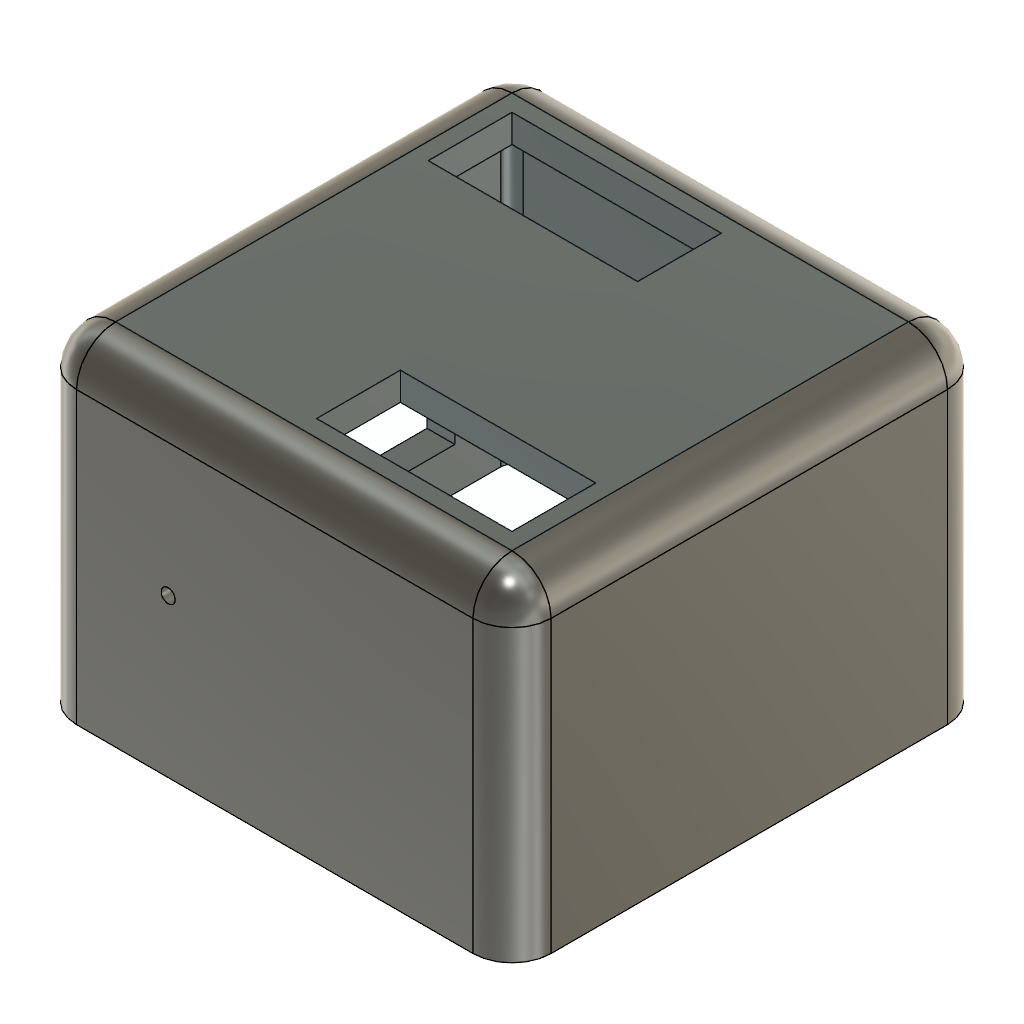
base (Autodesk Fusion 360 design; units mm, degrees)
part number: 2026-10-28-17-51-00-344
Autodesk Fusion 360 part; units mm, degrees
sketch "Sketch1" plane through (0, 0, 0) normal (0, 0, 1) x (1, 0, 0)
  line L0 (-100, 100) -> (50, 100)
  line L1 (50, 100) -> (50, -50)
  line L2 (50, -50) -> (-100, -50)
  line L3 (-100, -50) -> (-100, 100)
  dimension "d1" = 150
  dimension "d2" = 150
  constraint horizontal L0
  constraint vertical L1
  constraint horizontal L2
  constraint vertical L3
  measures "d1" distance of L0.start L0.end
  measures "d2" distance of L0.start L2.end
extrude "Extrude1" add sketch "Sketch1" along normal blind 8
fillet "Fillet1" radius 4 1 edges at (-25, 100, 8)
fillet "Fillet2" radius 4 3 edges at (50, 23, 8) (50, 98.8284, 6.8284) (50, 100, 2)
fillet "Fillet3" radius 4 3 edges at (-27, -50, 8) (48.8284, -50, 6.8284) (50, -50, 2)
fillet "Fillet4" radius 4 5 edges at (-100, 100, 2) (-100, 98.8284, 6.8284) (-100, 25, 8) (-100, -48.8284, 6.8284) (-100, -50, 2)
sketch "Sketch2" plane through (0, 0, 0) normal (0, 1, 0) x (1, 0, 0)
extrude "Extrude2" add 1 faces at (-50, 48.6667, 0) along direction (0, 0, -1) blind 100
shell "Shell1" thickness 10 outward yes removed faces 1 at (-50, 48.6667, -100)
sketch "Sketch3" plane through (0, 0, 18) normal (0, 0, 1) x (-1, 0, 0)
  line L0 (96, -96) -> (96, 46)
  line L1 (96, 46) -> (-46, 46)
  line L2 (-46, 46) -> (-46, -96)
  line L3 (-46, -96) -> (96, -96)
  line L4 (-40, 40) -> (30, 40)
  line L5 (30, 40) -> (30, 10)
  line L6 (30, 10) -> (-40, 10)
  line L7 (-40, 10) -> (-40, 40)
  line L8 (90, -90) -> (15, -90)
  line L9 (15, -90) -> (15, -60)
  line L10 (15, -60) -> (90, -60)
  line L11 (90, -60) -> (90, -90)
  dimension "d16" = 75
  dimension "d17" = 30
  constraint horizontal L4
  constraint vertical L5
  constraint horizontal L6
  constraint vertical L7
  constraint horizontal L8
  constraint vertical L9
  constraint horizontal L10
  constraint vertical L11
  measures "d16" distance of L8.start L8.end
  measures "d17" distance of L8.start L10.end
extrude "Extrude3" cut sketch "Sketch3" along normal blind 0 and the other way blind 10 contours L4 L5 L6 L7
sketch "Sketch4" plane through (0, 0, 18) normal (0, 0, 1) x (-1, 0, 0)
  line L0 (30, 40) -> (30, 10)
  line L1 (30, 10) -> (-40, 10)
  line L2 (-40, 10) -> (-40, 40)
  line L3 (-40, 40) -> (30, 40)
  line L4 (96, -96) -> (96, 46)
  line L5 (96, 46) -> (-46, 46)
  line L6 (-46, 46) -> (-46, -96)
  line L7 (-46, -96) -> (96, -96)
  line L8 (90, -90) -> (15, -90)
  line L9 (15, -90) -> (15, -60)
  line L10 (15, -60) -> (90, -60)
  line L11 (90, -60) -> (90, -90)
  dimension "d22" = 75
  dimension "d23" = 30
  constraint horizontal L8
  constraint vertical L9
  constraint horizontal L10
  constraint vertical L11
  measures "d22" distance of L8.start L8.end
  measures "d23" distance of L8.start L10.end
extrude "Extrude4" cut sketch "Sketch4" along normal blind 0 and the other way blind 10 contours L8 L9 L10 L11
sketch "Sketch5" plane through (0, 0, 18) normal (0, 0, 1) x (-1, 0, 0)
  line L0 (15, -90) -> (15, -60)
  line L1 (15, -60) -> (90, -60)
  line L2 (90, -60) -> (90, -90)
  line L3 (90, -90) -> (15, -90)
  line L4 (30, 40) -> (30, 10)
  line L5 (30, 10) -> (-40, 10)
  line L6 (-40, 10) -> (-40, 40)
  line L7 (-40, 40) -> (30, 40)
  line L8 (96, -96) -> (96, 46)
  line L9 (96, 46) -> (-46, 46)
  line L10 (-46, 46) -> (-46, -96)
  line L11 (-46, -96) -> (96, -96)
sketch "Sketch6" plane through (-110, 0, 0) normal (-1, 0, 0) x (0, -1, 0)
  line L0 (-96, 4) -> (-96, -100)
  line L1 (-96, -100) -> (46, -100)
  line L2 (46, -100) -> (46, 4)
  line L3 (46, 4) -> (-96, 4)
  line L4 (-79.5389, -20) -> (28.4611, -20)
  line L5 (28.4611, -20) -> (28.4611, -84.8)
  line L6 (28.4611, -84.8) -> (-79.5389, -84.8)
  line L7 (-79.5389, -84.8) -> (-79.5389, -20)
  dimension "d28" = 108
  dimension "d29" = 64.8
  constraint horizontal L4
  constraint vertical L5
  constraint horizontal L6
  constraint vertical L7
  measures "d28" distance of L4.start L4.end
  measures "d29" distance of L4.start L6.end
extrude "Extrude5" cut sketch "Sketch6" along normal blind 1 and the other way blind 11 contours L4 L5 L6 L7
sketch "Sketch7" plane through (0, -60, 0) normal (0, -1, 0) x (1, 0, 0)
  line L0 (-96, 4) -> (-96, -100)
  line L1 (-96, -100) -> (46, -100)
  line L2 (46, -100) -> (46, 4)
  line L3 (46, 4) -> (-96, 4)
  circle A0 centre (-63.1667, -43.5712) radius 2.5
  dimension "d34" = 5
  measures "d34" diameter of A0
extrude "Extrude6" cut sketch "Sketch7" along normal blind 0 and the other way blind 10 contours A0
